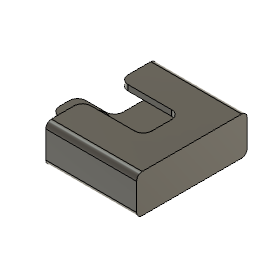
ironHolder (Autodesk Fusion 360 design; units mm, degrees)
part number: 2026-08-10-19-56-16-923
Autodesk Fusion 360 part; units mm, degrees
sketch "Sketch1" plane through (0, 0, 0) normal (0, 0, 1) x (1, 0, 0)
  line L0 (-28, 37) -> (62, 37)
  line L1 (62, 37) -> (62, 18)
  line L2 (62, 18) -> (-28, 18)
  line L3 (-28, 18) -> (-28, 37)
  dimension "d1" = 90
  dimension "d2" = 19
  constraint horizontal L0
  constraint vertical L1
  constraint horizontal L2
  constraint vertical L3
  measures "d1" distance of L0.start L0.end
  measures "d2" distance of L0.start L2.end
extrude "Extrude1" add sketch "Sketch1" along normal blind 6
sketch "Sketch2" plane through (0, 0, 6) normal (0, 0, 1) x (-1, 0, 0)
  line L0 (28, -37) -> (28, -18)
  line L1 (28, -18) -> (-62, -18)
  line L2 (-62, -18) -> (-62, -37)
  line L3 (-62, -37) -> (28, -37)
ref_plane "WorkPlane1" through (17, 27.5, 6) normal (0, 0, 1) x (-1, 0, 0)
sketch "Sketch3" plane through (0, 0, 6) normal (0, 0, 1) x (1, 0, 0)
  line L0 (17, 37) -> (17, 18)
  circle A0 centre (-8, 27.5) radius 8.9
  circle A1 centre (42, 27.5) radius 8.9
  circle A2 centre (-8, 27.5) radius 3.65
  circle A3 centre (42, 27.5) radius 3.65
  dimension "d13" = 17.8
  dimension "d14" = 17.8
  dimension "d15" = 7.3
  dimension "d16" = 7.3
  constraint vertical L0
  constraint concentric A0 A2
  constraint concentric A1 A3
  measures "d13" diameter of A0
  measures "d14" diameter of A1
  measures "d15" diameter of A2
  measures "d16" diameter of A3
extrude "Extrude2" cut sketch "Sketch3" against normal blind 7 contours A2 | A3
extrude "Extrude3" cut sketch "Sketch3" against normal blind 3
sketch "Sketch4" plane through (0, 0, 0) normal (0, 0, 1) x (1, 0, 0)
  line L0 (-21, 37) -> (55, 37)
  line L1 (55, 37) -> (55, 39)
  line L2 (55, 39) -> (-21, 39)
  line L3 (-21, 39) -> (-21, 37)
  dimension "d21" = 76
  dimension "d22" = 2
  constraint horizontal L0
  constraint vertical L1
  constraint horizontal L2
  constraint vertical L3
  measures "d21" distance of L0.start L0.end
  measures "d22" distance of L0.start L2.end
sketch "Sketch7" plane through (0, 0, 6) normal (0, 0, 1) x (-1, 0, 0)
  circle A0 centre (-42, -27.5) radius 8.9
  circle A1 centre (8, -27.5) radius 8.9
  line L0 (28, -18) -> (-62, -18)
  line L1 (-62, -18) -> (-62, -37)
  line L2 (-62, -37) -> (28, -37)
  line L3 (28, -37) -> (28, -18)
  line L4 (-62, -18) -> (2, -18)
  line L5 (2, -18) -> (2, 11.5)
  line L6 (2, 11.5) -> (-62, 11.5)
  line L7 (-62, 11.5) -> (-62, -18)
  line L8 (-62, -37) -> (2, -37)
  line L9 (2, -37) -> (2, -66.5)
  line L10 (2, -66.5) -> (-62, -66.5)
  line L11 (-62, -66.5) -> (-62, -37)
  dimension "d37" = 64
  dimension "d38" = 29.5
  dimension "d39" = 64
  dimension "d40" = 29.5
  constraint horizontal L4
  constraint vertical L5
  constraint horizontal L6
  constraint vertical L7
  constraint coincident L0.end L1.start
  constraint horizontal L8
  constraint vertical L9
  constraint horizontal L10
  constraint vertical L11
  constraint coincident L1.end L2.start
  measures "d37" distance of L0.end L4.end
  measures "d38" distance of L0.end L6.end
  measures "d39" distance of L1.end L8.end
  measures "d40" distance of L1.end L10.end
extrude "Extrude7" add sketch "Sketch7" against normal blind 6 contours L0 L4 L5 L6 L7 | L2 L8 L9 L10 L11
sketch "Sketch8" plane through (0, 0, 6) normal (0, 0, 1) x (-1, 0, 0)
  circle A0 centre (-42, -27.5) radius 8.9
  circle A1 centre (8, -27.5) radius 8.9
  line L0 (28, -18) -> (2, -18)
  line L1 (2, -18) -> (2, 11.5)
  line L2 (2, 11.5) -> (-62, 11.5)
  line L3 (-62, 11.5) -> (-62, -66.5)
  line L4 (-62, -66.5) -> (2, -66.5)
  line L5 (2, -66.5) -> (2, -37)
  line L6 (2, -37) -> (28, -37)
  line L7 (28, -37) -> (28, -18)
  line L8 (-62, -66.5) -> (-58, -66.5)
  line L9 (-58, -66.5) -> (-58, 11.5)
  line L10 (-58, 11.5) -> (-62, 11.5)
  line L11 (-62, 11.5) -> (-62, -66.5)
  dimension "d43" = 4
  dimension "d44" = 78
  constraint horizontal L8
  constraint vertical L9
  constraint horizontal L10
  constraint vertical L11
  constraint coincident L3.end L4.start
  measures "d43" distance of L3.end L8.end
  measures "d44" distance of L3.end L2.end
extrude "Extrude8" add sketch "Sketch8" along normal blind 21 contours L2 L3 L4 L8 L9 L10 L11
sketch "Sketch9" plane through (58, 0, 0) normal (-1, 0, 0) x (0, -1, 0)
  line L0 (-66.5, 6) -> (11.5, 6)
  line L1 (11.5, 6) -> (11.5, 27)
  line L2 (11.5, 27) -> (-66.5, 27)
  line L3 (-66.5, 27) -> (-66.5, 6)
  line L4 (-66.5, 27) -> (11.5, 27)
  line L5 (11.5, 27) -> (11.5, 23)
  line L6 (11.5, 23) -> (-66.5, 23)
  line L7 (-66.5, 23) -> (-66.5, 27)
  dimension "d47" = 78
  dimension "d48" = 4
  constraint horizontal L4
  constraint vertical L5
  constraint horizontal L6
  constraint vertical L7
  constraint coincident L2.end L3.start
  measures "d47" distance of L2.end L1.end
  measures "d48" distance of L2.end L6.end
extrude "Extrude9" add sketch "Sketch9" along normal blind 60 contours L1 L2 L3 L4 L5 L6 L7
sketch "Sketch10" plane through (0, -11.5, 0) normal (0, -1, 0) x (1, 0, 0)
  line L0 (58, 6) -> (-2, 6)
  line L1 (-2, 6) -> (-2, 0)
  line L2 (-2, 0) -> (62, 0)
  line L3 (62, 0) -> (62, 27)
  line L4 (62, 27) -> (-2, 27)
  line L5 (-2, 27) -> (-2, 23)
  line L6 (-2, 23) -> (58, 23)
  line L7 (58, 23) -> (58, 6)
  line L8 (58, 23) -> (-2, 23)
  line L9 (-2, 23) -> (-2, 6)
  line L10 (-2, 6) -> (58, 6)
  line L11 (58, 6) -> (58, 23)
  dimension "d51" = 60
  constraint horizontal L8
  constraint vertical L9
  constraint horizontal L10
  constraint vertical L11
  constraint coincident L0 L1.start
  constraint coincident L6.end L7.start
  measures "d51" distance of L6.end L5.end
extrude "Extrude10" add sketch "Sketch10" against normal blind 4 contours L0 L6 L7 L8 L9 L10 L11
sketch "Sketch11" plane through (0, 66.5, 0) normal (0, 1, 0) x (-1, 0, 0)
  line L0 (2, 6) -> (-58, 6)
  line L1 (-58, 6) -> (-58, 23)
  line L2 (-58, 23) -> (2, 23)
  line L3 (2, 23) -> (2, 27)
  line L4 (2, 27) -> (-62, 27)
  line L5 (-62, 27) -> (-62, 0)
  line L6 (-62, 0) -> (2, 0)
  line L7 (2, 0) -> (2, 6)
  line L8 (-58, 23) -> (2, 23)
  line L9 (2, 23) -> (2, 6)
  line L10 (2, 6) -> (-58, 6)
  line L11 (-58, 6) -> (-58, 23)
  constraint horizontal L8
  constraint vertical L9
  constraint horizontal L10
  constraint vertical L11
  constraint coincident L0.start L7.end
  constraint coincident L1.end L2.start
extrude "Extrude11" add sketch "Sketch11" against normal blind 4 contours L0 L1 L2 L8 L9 L10 L11
sketch "Sketch12" plane through (0, 0, 27) normal (0, 0, 1) x (-1, 0, 0)
  line L0 (-62, 11.5) -> (-62, -66.5)
  line L1 (-62, -66.5) -> (2, -66.5)
  line L2 (2, -66.5) -> (2, 11.5)
  line L3 (2, 11.5) -> (-62, 11.5)
  line L4 (2, 11.5) -> (-62, 11.5)
  line L5 (-62, 11.5) -> (-62, -14.5)
  line L6 (-62, -14.5) -> (2, -14.5)
  line L7 (2, -14.5) -> (2, 11.5)
  line L8 (2, -66.5) -> (-62, -66.5)
  line L9 (-62, -66.5) -> (-62, -40.5)
  line L10 (-62, -40.5) -> (2, -40.5)
  line L11 (2, -40.5) -> (2, -66.5)
  line L12 (-62, -14.5) -> (-40.7, -14.5)
  line L13 (-40.7, -14.5) -> (-40.7, -40.5)
  line L14 (-40.7, -40.5) -> (-62, -40.5)
  line L15 (-62, -40.5) -> (-62, -14.5)
  dimension "d56" = 64
  dimension "d57" = 26
  dimension "d58" = 64
  dimension "d59" = 26
  dimension "d62" = 21.3
  dimension "d63" = 26
  constraint horizontal L4
  constraint vertical L5
  constraint horizontal L6
  constraint vertical L7
  constraint coincident L2.end L3.start
  constraint horizontal L8
  constraint vertical L9
  constraint horizontal L10
  constraint vertical L11
  constraint coincident L1.end L2.start
  constraint horizontal L12
  constraint vertical L13
  constraint horizontal L14
  constraint vertical L15
  measures "d56" distance of L2.end L0.start
  measures "d57" distance of L2.end L6.end
  measures "d58" distance of L1.end L0.end
  measures "d59" distance of L1.end L10.end
  measures "d62" distance of L5.end L12.end
  measures "d63" distance of L5.end L9.end
extrude "Extrude12" cut sketch "Sketch12" against normal blind 4 contours L2 L6 L10 L13
fillet "Fillet3" radius 6 1 edges at (-2, 18, 3)
fillet "Fillet4" radius 6 3 edges at (-2, 40.5, 25) (40.7, 40.5, 25) (-2, 14.5, 25)
fillet "Fillet5" radius 6 2 edges at (-28, 18, 3) (40.7, 14.5, 25)
fillet "Fillet6" radius 6 2 edges at (-28, 37, 3) (-2, 37, 3)
fillet "Fillet7" radius 4 3 edges at (30, -11.5, 0) (30, -11.5, 27) (30, 66.5, 27)
fillet "Fillet8" radius 4 1 edges at (30, 66.5, 0)
